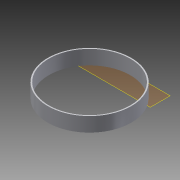
# Autodesk Inventor part: Ball_Base
Saved by Autodesk Inventor 2013 (Build 170138000, 138)
## iProperties
Created: 2013-10-01
Part Number: Ball_Base
Material: Generic
Document SubType Name: Modeling
Designer: Jeff
Density: 1 g/cm^3
Author: Jeff
Autodesk Inventor part; units mm, degrees
ref_plane "YZ Plane" through (0, 0, 0) normal (1, 0, 0) x (0, 1, 0)
ref_plane "XZ Plane" through (0, 0, 0) normal (0, 1, 0) x (-1, 0, 0)
ref_plane "XY Plane" through (0, 0, 0) normal (0, 0, 1) x (1, 0, 0)
ref_plane "Work Plane1" through (0, 97.8105, 0) normal (0, 0, 1) x (1, 0, 0)
sketch "Sketch1" plane through (0, 97.8105, 0) normal (0, 0, 1) x (1, 0, 0)
  arc A0 (57.7606, -9.3615) -> (-57.7606, -9.3615) centre (0, -48.9052) ccw projected
  circle A1 centre (0, -48.9052) radius 70
  circle A2 centre (0, -48.9052) radius 68
  point P0 (0, -97.8105)
  dimension "d0" = 140
  dimension "d1" = 2
  constraints: 2 centre point
  measures "d0" diameter of A1
  measures "d1" radial gap between concentric circles of A1 A2
extrude "Extrusion1" add sketch "Sketch1" along normal blind 24
body "Solid1"
